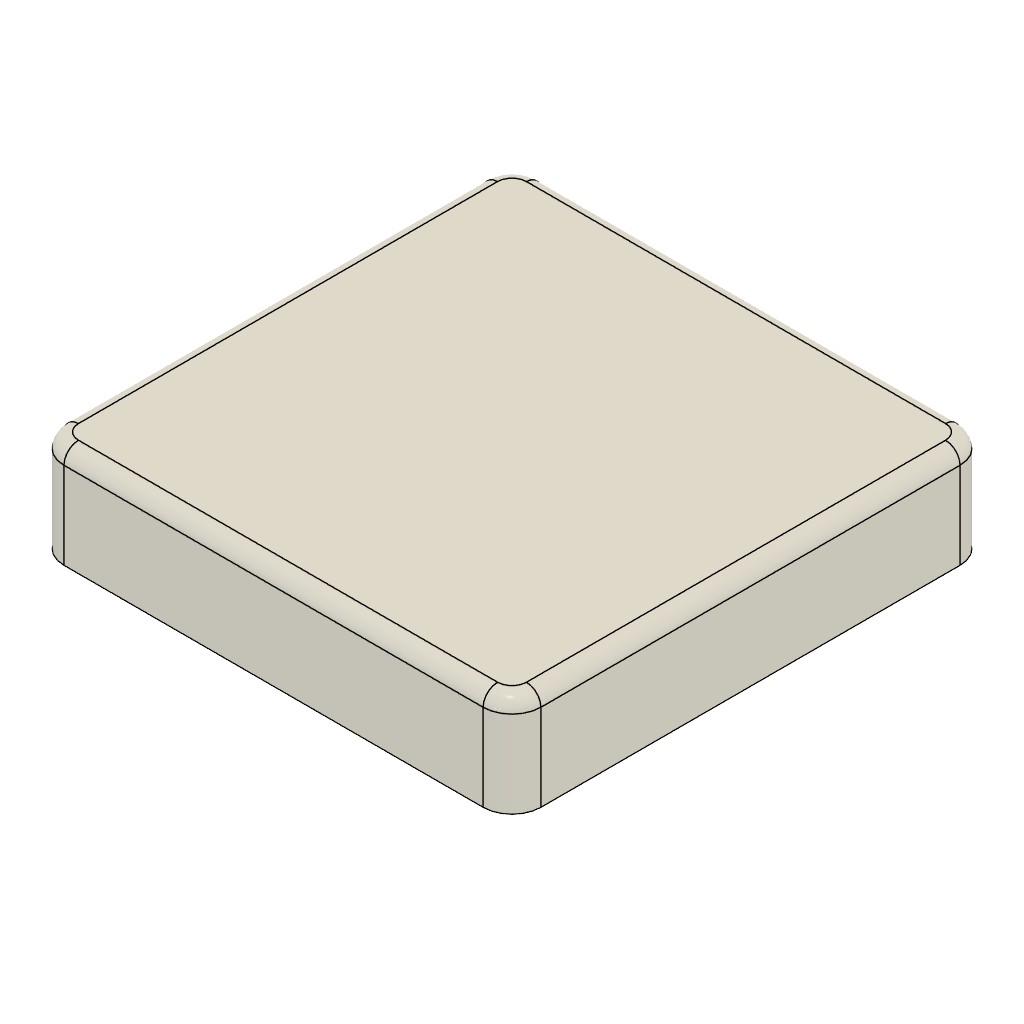
Assembly (Castor) (Autodesk Fusion 360 archive; units mm, degrees)
design "Keycap (1u)" references "_Globals"
part number: 2026-10-16-12-48-24-599
Autodesk Fusion 360 part; units mm, degrees
(part 1 of 5)
derive "Derived from _Globals"
sketch "Sketch1" plane through (0, 0, 0) normal (0, 1, 0) x (1, 0, 0)
  line L0 (-8.25, -8.25) -> (8.25, -8.25)
  line L1 (8.25, -8.25) -> (8.25, 8.25)
  line L2 (8.25, 8.25) -> (-8.25, 8.25)
  line L3 (-8.25, 8.25) -> (-8.25, -8.25)
  line L4 (-8.25, -8.25) -> (8.25, 8.25) construction
  line L5 (8.25, -8.25) -> (-8.25, 8.25) construction
  dimension "d17" = 16.5
  dimension "d18" = 16.5
  constraint horizontal L0
  constraint perpendicular L0 L1
  constraint parallel L0 L2
  constraint parallel L1 L3
  constraint coincident L4 origin
  constraint coincident L5 origin
  measures "d17" distance of L1.end L2.end
  measures "d18" distance of L0.end L1.end
extrude "Extrude1" add sketch "Sketch1" along normal blind 3.5
fillet "Fillet1" radius 1 4 edges at (8.25, 1.75, -8.25) (-8.25, 1.75, -8.25) (-8.25, 1.75, 8.25) (8.25, 1.75, 8.25)
fillet "Fillet2" radius 0.5 8 edges at (7.9571, 3.5, -7.9571) (0, 3.5, -8.25) (-7.9571, 3.5, -7.9571) (-8.25, 3.5, 0) (-7.9571, 3.5, 7.9571) (0, 3.5, 8.25) (7.9571, 3.5, 7.9571) (8.25, 3.5, 0)
sketch "Sketch2" plane through (0, 0, 0) normal (0, -1, 0) x (1, 0, 0)
  arc A0 (8.25, 7.25) -> (7.25, 8.25) centre (7.25, 7.25) ccw
  line L0 (7.25, 8.25) -> (-7.25, 8.25)
  arc A1 (-7.25, 8.25) -> (-8.25, 7.25) centre (-7.25, 7.25) ccw
  line L1 (-8.25, 7.25) -> (-8.25, -7.25)
  arc A2 (-8.25, -7.25) -> (-7.25, -8.25) centre (-7.25, -7.25) ccw
  line L2 (-7.25, -8.25) -> (7.25, -8.25)
  arc A3 (7.25, -8.25) -> (8.25, -7.25) centre (7.25, -7.25) ccw
  line L3 (8.25, -7.25) -> (8.25, 7.25)
  line L4 (-7.25, -7.25) -> (7.25, -7.25)
  line L5 (7.25, -7.25) -> (7.25, 7.25)
  line L6 (7.25, 7.25) -> (-7.25, 7.25)
  line L7 (-7.25, 7.25) -> (-7.25, -7.25)
extrude "Extrude2" cut sketch "Sketch2" against normal blind 2.05 contours L4 L5 L6 L7
fillet "Fillet3" radius 0.5 4 edges at (-7.25, 1.025, 7.25) (7.25, 1.025, 7.25) (7.25, 1.025, -7.25) (-7.25, 1.025, -7.25)
sketch "Sketch3" plane through (0, 2.05, 0) normal (0, -1, 0) x (1, 0, 0)
  arc A0 (-7.25, -6.75) -> (-6.75, -7.25) centre (-6.75, -6.75) ccw
  line L0 (-6.75, -7.25) -> (6.75, -7.25)
  arc A1 (6.75, -7.25) -> (7.25, -6.75) centre (6.75, -6.75) ccw
  line L1 (7.25, -6.75) -> (7.25, 6.75)
  arc A2 (7.25, 6.75) -> (6.75, 7.25) centre (6.75, 6.75) ccw
  line L2 (6.75, 7.25) -> (-6.75, 7.25)
  arc A3 (-6.75, 7.25) -> (-7.25, 6.75) centre (-6.75, 6.75) ccw
  line L3 (-7.25, 6.75) -> (-7.25, -6.75)
  circle A4 centre (0, 0) radius 2.7
  line L4 (0, 0) -> (0, 2.05) construction
  line L5 (-0.7, 2.05) -> (0.7, 2.05)
  line L6 (0.7, 2.05) -> (0.7, 0.7)
  line L7 (0.7, 0.7) -> (2.05, 0.7)
  line L8 (-2.05, -0.7) -> (-2.05, 0.7)
  line L9 (-2.05, 0.7) -> (-0.7, 0.7)
  line L10 (-0.7, 0.7) -> (-0.7, 2.05)
  line L11 (0.7, -2.05) -> (-0.7, -2.05)
  line L12 (-0.7, -2.05) -> (-0.7, -0.7)
  line L13 (-0.7, -0.7) -> (-2.05, -0.7)
  line L14 (2.05, 0.7) -> (2.05, -0.7)
  line L15 (2.05, -0.7) -> (0.7, -0.7)
  line L16 (0.7, -0.7) -> (0.7, -2.05)
  dimension "d32" = 5.4
  dimension "d33" = 2.05
  dimension "d34" = 1.4
  dimension "d35" = 1.35
  dimension "d36" = 1.35
  dimension "d38" = 360
  constraint coincident A4.centre L4.start
  constraint vertical L4
  constraint horizontal L5
  constraint midpoint L4.end L5
  constraint perpendicular L5 L6
  constraint perpendicular L6 L7
  measures "d32" diameter of A4
  measures "d33" distance of A4.centre L4.end
  measures "d34" distance of L5.start L5.end
  measures "d35" distance of L5.end L6.end
  measures "d36" distance of L6.end L7.end
extrude "Extrude3" add sketch "Sketch3" along normal blind 3.35 contours A4
fillet "Fillet4" radius 0.1 1 edges at (-2.5173, -1.3, -0.9764)
fillet "Fillet5" radius 0.1 4 edges at (0.7, 0.375, -0.7) (-0.7, 0.375, -0.7) (0.7, 0.375, 0.7) (-0.7, 0.375, 0.7)
equation "keycap_size_Ref = 16.5 mm"
equation "keycap_thickness_Ref = 3.5 mm" comment "Keycap thickness without stem"
equation "keycap_full_thickness_Ref = 4.8 mm" comment "Keycap thickness from stem to top"
equation "keycap_top_fillet_Ref1 = 0.5 mm"
equation "keycap_side_fillet_Ref1 = 1 mm"
equation "stem_fillet_Ref = 0.1 mm"
equation "stem_diameter_Ref = 5.5 mm"
equation "stem_cross_length_Ref = 4 mm"
equation "stem_cross_width_Ref = 1.3 mm"
equation "stem_offset_Ref = 0.1 mm"
equation "d17 = keycap_size_Ref"
equation "d18 = keycap_size_Ref"
equation "d19 = keycap_thickness_Ref"
equation "keycap_side_width_Ref = 1 mm"
equation "d23 = keycap_side_fillet_Ref1"
equation "d25 = keycap_top_fillet_Ref1"
equation "d26 = -keycap_side_width_Ref"
equation "keycap_inner_thickness_Ref = keycap_full_thickness_Ref - 3.35 mm"
equation "d28 = -( keycap_thickness_Ref - keycap_inner_thickness_Ref )"
equation "d31 = keycap_side_fillet_Ref1 * 0.5"
equation "d32 = stem_diameter_Ref - stem_offset_Ref"
equation "d33 = ( stem_cross_length_Ref + stem_offset_Ref ) * 0.5"
equation "d34 = stem_cross_width_Ref + stem_offset_Ref"
equation "d35 = ( stem_cross_length_Ref + stem_offset_Ref ) * 0.5 - ( stem_cross_width_Ref + stem_offset_Ref ) * 0.5"
equation "d36 = ( stem_cross_length_Ref + stem_offset_Ref ) * 0.5 - ( stem_cross_width_Ref + stem_offset_Ref ) * 0.5"
equation "d39 = keycap_full_thickness_Ref - keycap_inner_thickness_Ref"
equation "d42 = stem_fillet_Ref"
equation "d44 = stem_fillet_Ref"
equation "switch_size_Ref = 19.05 mm"
named bodies: "Main"

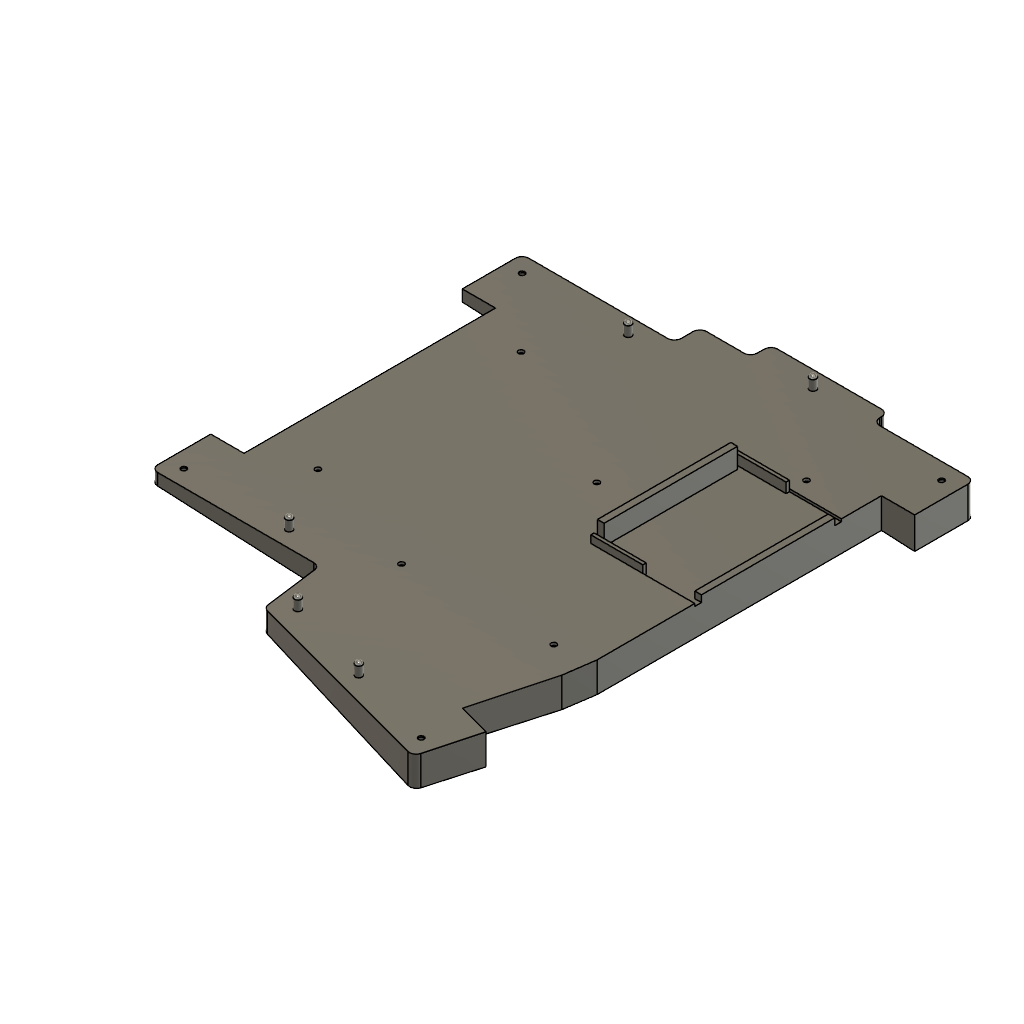
design "Case Bottom (Castor)" references "_Globals"
part number: 2026-10-18-17-09-08-420
Autodesk Fusion 360 part; units mm, degrees
derive "ExternalDerived1"
sketch "Sketch1" plane through (0, 0, 0) normal (0, 1, 0) x (1, 0, 0)
  line L0 (-9.525, 57.15) -> (-66.675, 57.15) construction
  line L1 (-66.675, 57.15) -> (-66.675, -57.15) construction
  line L2 (-66.675, -57.15) -> (-9.525, -57.15) construction
  line L3 (66.675, -45.72) -> (66.675, 57.15) construction
  line L4 (-66.675, 57.15) -> (-9.525, 57.15) construction
  line L5 (-9.525, 57.15) -> (-9.525, 66.675) construction
  line L6 (-9.525, 66.675) -> (9.525, 66.675) construction
  line L7 (9.525, 66.675) -> (9.525, 74.295) construction
  line L8 (9.525, 74.295) -> (28.575, 74.295) construction
  line L9 (28.575, 74.295) -> (28.575, 68.58) construction
  line L10 (28.575, 68.58) -> (66.675, 68.58) construction
  line L11 (66.675, 68.58) -> (66.675, 57.15) construction
  line L12 (-66.675, -57.15) -> (-9.525, -57.15) construction
  line L13 (-9.525, -57.15) -> (-9.525, -47.625) construction
  line L14 (-9.525, -47.625) -> (9.525, -47.625) construction
  line L15 (9.525, -47.625) -> (9.525, -45.72) construction
  line L16 (9.525, -45.72) -> (66.675, -45.72) construction
  line L17 (9.525, -47.625) -> (9.525, -47.73) construction
  line L18 (9.525, -47.73) -> (9.59, -47.73) construction
  line L19 (9.59, -47.73) -> (9.7259, -47.2229) construction
  line L20 (9.7259, -47.2229) -> (9.2188, -47.087) construction
  line L21 (9.2188, -47.087) -> (27.6197, -52.0175) construction
  line L22 (27.6197, -52.0175) -> (22.6892, -70.4184) construction
  line L23 (22.6892, -70.4184) -> (4.2883, -65.4879) construction
  line L24 (4.2883, -65.4879) -> (9.2188, -47.087) construction
  line L25 (27.6197, -52.0175) -> (64.4214, -61.8785) construction
  line L26 (64.4214, -61.8785) -> (54.5604, -98.6803) construction
  line L27 (54.5604, -98.6803) -> (-0.6422, -83.8888) construction
  line L28 (-0.6422, -83.8888) -> (4.2883, -65.4879) construction
  line L29 (-66.675, -57.15) -> (-69.15, -57.15) construction
  line L30 (-69.15, -57.15) -> (-69.15, -59.625) construction
  line L31 (-9.525, -57.15) -> (-7.05, -57.15) construction
  line L32 (-7.05, -57.15) -> (-7.05, -59.625) construction
  line L33 (-0.6422, -83.8888) -> (-1.2828, -86.2794) construction
  line L34 (-1.2828, -86.2794) -> (-3.6735, -85.6389) construction
  line L35 (54.5604, -98.6803) -> (53.9198, -101.071) construction
  line L36 (53.9198, -101.071) -> (56.3105, -101.7115) construction
  line L37 (64.4214, -61.8785) -> (65.062, -59.4879) construction
  line L38 (65.062, -59.4879) -> (67.4527, -60.1284) construction
  line L39 (66.675, -45.72) -> (66.675, -48.195) construction
  line L40 (66.675, -48.195) -> (69.15, -48.195) construction
  line L41 (66.675, 68.58) -> (66.675, 71.055) construction
  line L42 (66.675, 71.055) -> (69.15, 71.055) construction
  line L43 (28.575, 68.58) -> (31.05, 68.58) construction
  line L44 (31.05, 68.58) -> (31.05, 71.055) construction
  line L45 (28.575, 74.295) -> (28.575, 76.77) construction
  line L46 (28.575, 76.77) -> (31.05, 76.77) construction
  line L47 (9.525, 74.295) -> (9.525, 76.77) construction
  line L48 (9.525, 76.77) -> (7.05, 76.77) construction
  line L49 (9.525, 66.675) -> (7.05, 66.675) construction
  line L50 (7.05, 66.675) -> (7.05, 69.15) construction
  line L51 (-9.525, 66.675) -> (-12, 66.675) construction
  line L52 (-12, 66.675) -> (-12, 69.15) construction
  line L53 (-9.525, 57.15) -> (-12, 57.15) construction
  line L54 (-12, 57.15) -> (-12, 59.625) construction
  line L55 (-66.675, 57.15) -> (-69.15, 57.15) construction
  line L56 (-69.15, 57.15) -> (-69.15, 59.625) construction
  line L57 (-69.15, 59.625) -> (-12, 59.625)
  line L58 (-12, 59.625) -> (-12, 69.15)
  line L59 (-12, 69.15) -> (7.05, 69.15)
  line L60 (7.05, 69.15) -> (7.05, 76.77)
  line L61 (31.05, 76.77) -> (7.05, 76.77)
  line L62 (31.05, 71.055) -> (31.05, 76.77)
  line L63 (31.05, 71.055) -> (69.15, 71.055)
  line L64 (69.15, 71.055) -> (69.15, -48.195)
  line L65 (69.15, -48.195) -> (67.4527, -60.1284)
  line L66 (67.4527, -60.1284) -> (56.3105, -101.7115)
  line L67 (56.3105, -101.7115) -> (-3.6735, -85.6389)
  line L68 (-3.6735, -85.6389) -> (-7.05, -59.625)
  line L69 (-7.05, -59.625) -> (-69.15, -59.625)
  line L70 (-69.15, -59.625) -> (-69.15, 59.625)
  line L71 (-22, 79.15) -> (-2.95, 79.15)
  line L72 (-2.95, 79.15) -> (-2.95, 86.77)
  line L73 (41.05, 86.77) -> (-2.95, 86.77)
  line L74 (41.05, 81.055) -> (41.05, 86.77)
  line L75 (41.05, 81.055) -> (79.15, 81.055)
  line L76 (79.15, 81.055) -> (79.15, -48.9026)
  line L77 (79.15, -48.9026) -> (77.2681, -62.1339)
  line L78 (77.2681, -62.1339) -> (63.3816, -113.959)
  line L79 (63.3816, -113.959) -> (-12.7285, -93.5653)
  line L80 (-12.7285, -93.5653) -> (-15.8359, -69.625)
  line L81 (-15.8359, -69.625) -> (-79.15, -69.625)
  line L82 (-79.15, -69.625) -> (-79.15, 69.625)
  line L83 (-79.15, 69.625) -> (-22, 69.625)
  line L84 (-22, 69.625) -> (-22, 79.15)
  line L85 (-66.675, 57.15) -> (-9.525, 57.15)
  line L86 (-9.525, 57.15) -> (-9.525, 66.675)
  line L87 (-9.525, 66.675) -> (9.525, 66.675)
  line L88 (9.525, 66.675) -> (9.525, 74.295)
  line L89 (28.575, 74.295) -> (9.525, 74.295)
  line L90 (28.575, 68.58) -> (28.575, 74.295)
  line L91 (28.575, 68.58) -> (66.675, 68.58)
  line L92 (66.675, 68.58) -> (66.675, -48.0199)
  line L93 (66.675, -48.0199) -> (65.0234, -59.6321)
  line L94 (65.0234, -59.6321) -> (54.5604, -98.6803)
  line L95 (54.5604, -98.6803) -> (-1.4324, -83.6771)
  line L96 (-1.4324, -83.6771) -> (-4.8755, -57.15)
  line L97 (-4.8755, -57.15) -> (-66.675, -57.15)
  line L98 (-66.675, -57.15) -> (-66.675, 57.15)
  line L99 (-66.675, 57.15) -> (-66.675, 47.15) construction
  line L100 (-66.675, 47.15) -> (-79.15, 47.15)
  line L101 (-66.675, -57.15) -> (-66.675, -47.15) construction
  line L102 (-66.675, -47.15) -> (-79.15, -47.15)
  line L103 (54.5604, -98.6803) -> (57.1486, -89.021) construction
  line L104 (57.1486, -89.021) -> (69.1985, -92.2498)
  line L105 (66.675, 68.58) -> (66.675, 58.58) construction
  line L106 (66.675, 58.58) -> (79.15, 58.58)
  dimension "d54" = 114.3
  dimension "d55" = 57.15
  dimension "d56" = 9.525
  dimension "d57" = 19.05
  dimension "d58" = 7.62
  dimension "d59" = 19.05
  dimension "d60" = 5.715
  dimension "d61" = 38.1
  dimension "d62" = 57.15
  dimension "d63" = 9.525
  dimension "d64" = 19.05
  dimension "d65" = 1.905
  dimension "d66" = 0.105
  dimension "d67" = 0.065
  dimension "d68" = 0.525
  dimension "d69" = 0.525
  dimension "d70" = 19.05
  dimension "d71" = 19.05
  dimension "d72" = 38.1
  dimension "d73" = 38.1
  dimension "d74" = 57.15
  dimension "d75" = 2.475
  dimension "d76" = 2.475
  dimension "d77" = 2.475
  dimension "d78" = 2.475
  dimension "d79" = 2.475
  dimension "d80" = 2.475
  dimension "d81" = 2.475
  dimension "d82" = 2.475
  dimension "d83" = 2.475
  dimension "d84" = 2.475
  dimension "d85" = 2.475
  dimension "d86" = 2.475
  dimension "d87" = 2.475
  dimension "d88" = 2.475
  dimension "d89" = 2.475
  dimension "d90" = 2.475
  dimension "d91" = 2.475
  dimension "d92" = 2.475
  dimension "d93" = 2.475
  dimension "d94" = 2.475
  dimension "d95" = 2.475
  dimension "d96" = 2.475
  dimension "d97" = 2.475
  dimension "d98" = 2.475
  dimension "d99" = 2.475
  dimension "d100" = 2.475
  dimension "d101" = 2.475
  dimension "d102" = 2.475
  dimension "d104" = 2.475
  dimension "d107" = 10
  dimension "d108" = 10
  dimension "d109" = 10
  dimension "d110" = 10
  constraint horizontal L0
  constraint perpendicular L0 L1
  constraint parallel L0 L2
  constraint parallel L1 L3
  constraint perpendicular L4 L5
  constraint perpendicular L5 L6
  constraint perpendicular L6 L7
  constraint perpendicular L7 L8
  constraint perpendicular L6 L9
  constraint perpendicular L9 L10
  constraint perpendicular L12 L13
  constraint perpendicular L13 L14
  constraint perpendicular L12 L15
  constraint perpendicular L3 L16
  constraint perpendicular L14 L17
  constraint perpendicular L15 L18
  constraint perpendicular L19 L20
  constraint collinear L20 L21
  constraint parallel L21 L23
  constraint parallel L22 L24
  constraint perpendicular L22 L23
  constraint perpendicular L22 L25
  constraint perpendicular L25 L26
  constraint perpendicular L26 L27
  constraint perpendicular L1 L29
  constraint perpendicular L29 L30
  constraint perpendicular L13 L31
  constraint perpendicular L31 L32
  constraint perpendicular L27 L33
  constraint perpendicular L28 L34
  constraint perpendicular L27 L35
  constraint perpendicular L35 L36
  constraint perpendicular L25 L37
  constraint perpendicular L37 L38
  constraint perpendicular L16 L39
  constraint perpendicular L3 L40
  constraint perpendicular L10 L41
  constraint perpendicular L11 L42
  constraint coincident L10 L43.end
  constraint perpendicular L43 L44
  constraint perpendicular L8 L45
  constraint perpendicular L45 L46
  constraint perpendicular L8 L47
  constraint perpendicular L47 L48
  constraint coincident L6 L49.end
  constraint perpendicular L6 L50
  constraint perpendicular L5 L51
  constraint perpendicular L51 L52
  constraint coincident L4 L53.end
  constraint perpendicular L53 L54
  constraint perpendicular L1 L55
  constraint perpendicular L4 L56
  constraint perpendicular L62 L63
  constraint coincident L98 L99.end
  constraint coincident L82 L100.end
  constraint perpendicular L82 L100
  constraint coincident L98 L101.end
  constraint coincident L82 L102.end
  constraint perpendicular L82 L102
  constraint coincident L26 L103.end
  constraint coincident L78 L104.end
  constraint perpendicular L78 L104
  constraint coincident L11 L105.end
  constraint coincident L76 L106.end
  constraint perpendicular L76 L106
  measures "d54" distance of L0.end L1.end
  measures "d55" distance of L0.end L0.start
  measures "d56" distance of L0.start L5.end
  measures "d57" distance of L5.end L6.end
  measures "d58" distance of L6.end L7.end
  measures "d59" distance of L7.end L8.end
  measures "d60" distance of L8.end L9.end
  measures "d61" distance of L9.end L10.end
  measures "d62" distance of L1.end L2.end
  measures "d63" distance of L2.end L13.end
  measures "d64" distance of L13.end L14.end
  measures "d65" distance of L14.end L15.end
  measures "d66" distance of L14.end L17.end
  measures "d67" distance of L17.end L18.end
  measures "d68" distance of L18.end L19.end
  measures "d69" distance of L19.end L20.end
  measures "d70" distance of L20.end L21.end
  measures "d71" distance of L20.end L23.end
  measures "d72" distance of L21.end L25.end
  measures "d73" distance of L25.end L26.end
  measures "d74" distance of L26.end L27.end
  measures "d75" distance of L1.end L29.end
  measures "d76" distance of L29.end L30.end
  measures "d77" distance of L2.end L31.end
  measures "d78" distance of L31.end L32.end
  measures "d79" distance of L27.end L33.end
  measures "d80" distance of L33.end L34.end
  measures "d81" distance of L26.end L35.end
  measures "d82" distance of L35.end L36.end
  measures "d83" distance of L25.end L37.end
  measures "d84" distance of L37.end L38.end
  measures "d85" distance of L3.start L39.end
  measures "d86" distance of L39.end L40.end
  measures "d87" distance of L10.end L41.end
  measures "d88" distance of L41.end L42.end
  measures "d89" distance of L9.end L43.end
  measures "d90" distance of L43.end L44.end
  measures "d91" distance of L8.end L45.end
  measures "d92" distance of L45.end L46.end
  measures "d93" distance of L7.end L47.end
  measures "d94" distance of L47.end L48.end
  measures "d95" distance of L6.end L49.end
  measures "d96" distance of L49.end L50.end
  measures "d97" distance of L5.end L51.end
  measures "d98" distance of L51.end L52.end
  measures "d99" distance of L0.start L53.end
  measures "d100" distance of L53.end L54.end
  measures "d101" distance of L0.end L55.end
  measures "d102" distance of L55.end L56.end
  measures "d107" distance of L0.end L99.end
  measures "d108" distance of L1.end L101.end
  measures "d109" distance of L26.end L103.end
  measures "d110" distance of L10.end L105.end
extrude "Extrude1" add sketch "Sketch1" against normal blind 11.8975
extrude "Extrude2" cut sketch "Sketch1" against normal through all contours L70 L98 L100 L102 | L70 L82 L100 L102 | L64 L65 L66 L92 L93 L94 L104 L106 | L64 L65 L66 L76 L77 L78 L104 L106
sketch "Sketch2" plane through (0, -11.8975, 0) normal (0, -1, 0) x (1, 0, 0)
  line L0 (-66.675, -47.15) -> (-79.15, -47.15)
  line L1 (-79.15, -47.15) -> (-79.15, -69.625)
  line L2 (-79.15, -69.625) -> (-22, -69.625)
  line L3 (-22, -69.625) -> (-22, -79.15)
  line L4 (-22, -79.15) -> (-2.95, -79.15)
  line L5 (-2.95, -79.15) -> (-2.95, -86.77)
  line L6 (-2.95, -86.77) -> (41.05, -86.77)
  line L7 (41.05, -86.77) -> (41.05, -81.055)
  line L8 (41.05, -81.055) -> (79.15, -81.055)
  line L9 (79.15, -81.055) -> (79.15, -58.58)
  line L10 (79.15, -58.58) -> (66.675, -58.58)
  line L11 (66.675, -58.58) -> (66.675, 48.0199)
  line L12 (66.675, 48.0199) -> (65.0234, 59.6321)
  line L13 (65.0234, 59.6321) -> (57.1486, 89.021)
  line L14 (57.1486, 89.021) -> (69.1985, 92.2498)
  line L15 (69.1985, 92.2498) -> (63.3816, 113.959)
  line L16 (63.3816, 113.959) -> (-12.7285, 93.5653)
  line L17 (-12.7285, 93.5653) -> (-15.8359, 69.625)
  line L18 (-15.8359, 69.625) -> (-79.15, 69.625)
  line L19 (-79.15, 69.625) -> (-79.15, 47.15)
  line L20 (-79.15, 47.15) -> (-66.675, 47.15)
  line L21 (-66.675, 47.15) -> (-66.675, -47.15)
  line L22 (79.15, -81.055) -> (79.15, -71.055) construction
  line L23 (79.15, -71.055) -> (69.15, -71.055) construction
  line L24 (69.15, -71.055) -> (79.15, -81.055) construction
  circle A0 centre (79.15, -81.055) radius 8.75 construction
  line L25 (-79.15, -69.625) -> (-69.15, -69.625) construction
  line L26 (-69.15, -69.625) -> (-69.15, -59.625) construction
  line L27 (-69.15, -59.625) -> (-79.15, -69.625) construction
  circle A1 centre (-79.15, -69.625) radius 8.75 construction
  line L28 (63.3816, 113.959) -> (53.7223, 111.3708) construction
  line L29 (53.7223, 111.3708) -> (56.3105, 101.7115) construction
  line L30 (56.3105, 101.7115) -> (63.3816, 113.959) construction
  circle A2 centre (63.3816, 113.959) radius 8.75 construction
  line L31 (-79.15, 69.625) -> (-69.15, 69.625) construction
  line L32 (-69.15, 69.625) -> (-69.15, 59.625) construction
  line L33 (-69.15, 59.625) -> (-79.15, 69.625) construction
  circle A3 centre (-79.15, 69.625) radius 8.75 construction
  circle A4 centre (-72.9628, 63.4378) radius 1.025
  circle A5 centre (-72.9628, 63.4378) radius 2.075
  circle A6 centre (59.0066, 106.3813) radius 2.075
  circle A7 centre (59.0066, 106.3813) radius 1.025
  circle A8 centre (72.9628, -74.8678) radius 2.075
  circle A9 centre (72.9628, -74.8678) radius 1.025
  circle A10 centre (-72.9628, -63.4378) radius 2.075
  circle A11 centre (-72.9628, -63.4378) radius 1.025
  line L34 (-69.15, -59.625) -> (-47.625, -59.625) construction
  line L35 (-47.625, -59.625) -> (-47.625, -37.725) construction
  line L36 (-69.15, 59.625) -> (-47.625, 59.625) construction
  line L37 (-47.625, 59.625) -> (-47.625, 38.475) construction
  line L38 (69.15, -71.055) -> (47.625, -71.055) construction
  line L39 (47.625, -71.055) -> (47.625, -49.53) construction
  line L40 (-47.625, -59.625) -> (8.975, -59.625) construction
  line L41 (8.975, -59.625) -> (8.975, -9.525) construction
  line L42 (69.15, -71.055) -> (69.15, 45.72) construction
  line L43 (69.15, 45.72) -> (53.5781, 45.72) construction
  line L44 (53.5781, 45.72) -> (53.5781, 51.1969) construction
  line L45 (-47.625, 59.625) -> (-1.1906, 59.625) construction
  line L46 (-1.1906, 59.625) -> (-1.1906, 53.5781) construction
  circle A12 centre (-1.1906, 53.5781) radius 1.025
  circle A13 centre (-1.1906, 53.5781) radius 1.75
  circle A14 centre (-47.625, 38.475) radius 1.025
  circle A15 centre (-47.625, 38.475) radius 1.75
  circle A16 centre (53.5781, 51.1969) radius 1.025
  circle A17 centre (53.5781, 51.1969) radius 1.75
  circle A18 centre (8.975, -9.525) radius 1.025
  circle A19 centre (8.975, -9.525) radius 1.75
  circle A20 centre (47.625, -49.53) radius 1.025
  circle A21 centre (47.625, -49.53) radius 1.75
  circle A22 centre (-47.625, -37.725) radius 1.025
  circle A23 centre (-47.625, -37.725) radius 1.75
  dimension "d112" = 10
  dimension "d113" = 10
  dimension "d114" = 17.5
  dimension "d115" = 10
  dimension "d116" = 10
  dimension "d117" = 17.5
  dimension "d118" = 10
  dimension "d119" = 10
  dimension "d120" = 17.5
  dimension "d121" = 10
  dimension "d122" = 10
  dimension "d123" = 17.5
  dimension "d124" = 2.05
  dimension "d125" = 4.15
  dimension "d126" = 4.15
  dimension "d127" = 2.05
  dimension "d128" = 4.15
  dimension "d129" = 2.05
  dimension "d130" = 4.15
  dimension "d131" = 2.05
  dimension "d134" = 21.525
  dimension "d135" = 21.9
  dimension "d138" = 21.525
  dimension "d139" = 21.15
  dimension "d140" = 21.525
  dimension "d141" = 21.525
  dimension "d142" = 56.6
  dimension "d146" = 50.1
  dimension "d147" = 116.775
  dimension "d148" = 15.5719
  dimension "d149" = 5.4769
  dimension "d150" = 46.4344
  dimension "d151" = 6.0469
  dimension "d152" = 2.05
  dimension "d153" = 3.5
  dimension "d154" = 2.05
  dimension "d155" = 3.5
  dimension "d156" = 2.05
  dimension "d157" = 3.5
  dimension "d158" = 2.05
  dimension "d159" = 3.5
  dimension "d160" = 2.05
  dimension "d161" = 3.5
  dimension "d162" = 2.05
  dimension "d163" = 3.5
  constraint coincident L8.end L9.start
  constraint perpendicular L8 L22
  constraint perpendicular L9 L23
  constraint coincident L1.end L2.start
  constraint coincident L2 L25.end
  constraint perpendicular L2 L26
  constraint coincident L15.end L16.start
  constraint coincident L16 L28.end
  constraint perpendicular L16 L29
  constraint coincident L18.end L19.start
  constraint coincident L18 L31.end
  constraint perpendicular L18 L32
  constraint coincident A3 A4.centre
  constraint coincident L33 A4.centre
  constraint concentric A4 A5
  constraint coincident A2 A6.centre
  constraint coincident L30 A6.centre
  constraint concentric A6 A7
  constraint coincident A0 A8.centre
  constraint coincident L24 A8.centre
  constraint concentric A8 A9
  constraint coincident A1 A10.centre
  constraint coincident L27 A10.centre
  constraint concentric A10 A11
  constraint perpendicular L26 L34
  constraint perpendicular L34 L35
  constraint perpendicular L32 L36
  constraint perpendicular L36 L37
  constraint parallel L23 L38
  constraint perpendicular L38 L39
  constraint perpendicular L35 L40
  constraint perpendicular L40 L41
  constraint perpendicular L38 L42
  constraint perpendicular L42 L43
  constraint perpendicular L43 L44
  constraint perpendicular L37 L45
  constraint perpendicular L45 L46
  constraint coincident L46.end A12.centre
  constraint concentric A12 A13
  constraint coincident L37.end A14.centre
  constraint concentric A14 A15
  constraint coincident L44.end A16.centre
  constraint concentric A16 A17
  constraint coincident L41.end A18.centre
  constraint concentric A18 A19
  constraint coincident L39.end A20.centre
  constraint concentric A20 A21
  constraint coincident L35.end A22.centre
  measures "d112" distance of L8.end L22.end
  measures "d113" distance of L22.end L23.end
  measures "d114" diameter of A0
  measures "d115" distance of L1.end L25.end
  measures "d116" distance of L25.end L26.end
  measures "d117" diameter of A1
  measures "d118" distance of L15.end L28.end
  measures "d119" distance of L28.end L29.end
  measures "d120" diameter of A2
  measures "d121" distance of L18.end L31.end
  measures "d122" distance of L31.end L32.end
  measures "d123" diameter of A3
  measures "d124" diameter of A4
  measures "d125" diameter of A5
  measures "d126" diameter of A6
  measures "d127" diameter of A7
  measures "d128" diameter of A8
  measures "d129" diameter of A9
  measures "d130" diameter of A10
  measures "d131" diameter of A11
  measures "d134" distance of L26.end L34.end
  measures "d135" distance of L34.end L35.end
  measures "d138" distance of L32.end L36.end
  measures "d139" distance of L36.end L37.end
  measures "d140" distance of L23.end L38.end
  measures "d141" distance of L38.end L39.end
  measures "d142" distance of L34.end L40.end
  measures "d146" distance of L40.end L41.end
  measures "d147" distance of L23.end L42.end
  measures "d148" distance of L42.end L43.end
  measures "d149" distance of L43.end L44.end
  measures "d150" distance of L36.end L45.end
  measures "d151" distance of L45.end L46.end
  measures "d152" diameter of A12
  measures "d153" diameter of A13
  measures "d154" diameter of A14
  measures "d155" diameter of A15
  measures "d156" diameter of A16
  measures "d157" diameter of A17
  measures "d158" diameter of A18
  measures "d159" diameter of A19
  measures "d160" diameter of A20
  measures "d161" diameter of A21
  measures "d162" diameter of A22
  measures "d163" diameter of A23
extrude "Extrude3" cut sketch "Sketch2" against normal through all contours A4 | A7 | A9 | A11 | A12 | A14 | A16 | A18 | A20 | A22
sketch "Sketch3" plane through (0, 0, 0) normal (0, 1, 0) x (-1, 0, 0)
  line L0 (79.15, -47.15) -> (66.675, -47.15)
  line L1 (66.675, -47.15) -> (66.675, 47.15)
  line L2 (66.675, 47.15) -> (79.15, 47.15)
  line L3 (79.15, 47.15) -> (79.15, 69.625)
  line L4 (79.15, 69.625) -> (15.8359, 69.625)
  line L5 (15.8359, 69.625) -> (12.7285, 93.5653)
  line L6 (12.7285, 93.5653) -> (-63.3816, 113.959)
  line L7 (-63.3816, 113.959) -> (-69.1985, 92.2498)
  line L8 (-69.1985, 92.2498) -> (-57.1486, 89.021)
  line L9 (-57.1486, 89.021) -> (-65.0234, 59.6321)
  line L10 (-65.0234, 59.6321) -> (-66.675, 48.0199)
  line L11 (-66.675, 48.0199) -> (-66.675, -58.58)
  line L12 (-66.675, -58.58) -> (-79.15, -58.58)
  line L13 (-79.15, -58.58) -> (-79.15, -81.055)
  line L14 (-79.15, -81.055) -> (-41.05, -81.055)
  line L15 (-41.05, -81.055) -> (-41.05, -86.77)
  line L16 (-41.05, -86.77) -> (2.95, -86.77)
  line L17 (2.95, -86.77) -> (2.95, -79.15)
  line L18 (2.95, -79.15) -> (22, -79.15)
  line L19 (22, -79.15) -> (22, -69.625)
  line L20 (22, -69.625) -> (79.15, -69.625)
  line L21 (79.15, -69.625) -> (79.15, -47.15)
  circle A0 centre (72.9628, -63.4378) radius 1.025
  circle A1 centre (-8.975, -9.525) radius 1.025
  circle A2 centre (1.1906, 53.5781) radius 1.025
  circle A3 centre (-53.5781, 51.1969) radius 1.025
  circle A4 centre (-47.625, -49.53) radius 1.025
  circle A5 centre (47.625, -37.725) radius 1.025
  circle A6 centre (72.9628, 63.4378) radius 1.025
  circle A7 centre (-59.0066, 106.3813) radius 1.025
  circle A8 centre (47.625, 38.475) radius 1.025
  circle A9 centre (-72.9628, -74.8678) radius 1.025
  line L22 (79.15, -69.625) -> (66.675, -69.625) construction
  line L23 (66.675, -69.625) -> (66.675, -57.15) construction
  line L24 (66.675, -57.15) -> (9.525, -57.15) construction
  line L25 (9.525, -57.15) -> (9.525, -69.625) construction
  line L26 (66.675, -57.15) -> (56.675, -57.15) construction
  line L27 (56.675, -57.15) -> (56.675, -69.625) construction
  line L28 (56.675, -63.3875) -> (9.525, -63.3875) construction
  circle A10 centre (33.1, -63.3875) radius 1.25
  line L29 (-19.05, -86.77) -> (-19.05, -74.295) construction
  circle A11 centre (-19.05, -80.5325) radius 1.25
  line L30 (-25.3265, 103.7622) -> (-28.5553, 91.7122) construction
  circle A12 centre (-26.9409, 97.7372) radius 1.25
  line L31 (-53.9198, 101.071) -> (3.6735, 85.6389) construction
  line L32 (3.6735, 85.6389) -> (12.7285, 93.5653) construction
  line L33 (3.6735, 85.6389) -> (-10.6659, 73.0867) construction
  line L34 (-57.1486, 89.021) -> (-54.5604, 98.6803) construction
  line L35 (-54.5604, 98.6803) -> (-53.9198, 101.071) construction
  line L36 (-54.5604, 98.6803) -> (1.4324, 83.6771) construction
  line L37 (79.15, 69.625) -> (66.675, 69.625) construction
  line L38 (66.675, 69.625) -> (66.675, 59.625) construction
  line L39 (66.675, 59.625) -> (66.675, 57.15) construction
  line L40 (66.675, 59.625) -> (7.05, 59.625) construction
  line L41 (7.05, 59.625) -> (15.8359, 69.625) construction
  line L42 (7.05, 59.625) -> (-0.857, 50.6253) construction
  line L43 (66.675, 57.15) -> (4.8755, 57.15) construction
  line L44 (4.8755, 57.15) -> (1.4324, 83.6771) construction
  line L45 (66.675, 69.625) -> (56.675, 69.625) construction
  line L46 (56.675, 69.625) -> (56.675, 57.15) construction
  line L47 (56.675, 63.3875) -> (10.3557, 63.3875) construction
  circle A13 centre (33.5154, 63.3875) radius 1.25
  line L48 (3.1539, 70.4135) -> (14.2822, 81.5952) construction
  line L49 (8.7181, 76.0044) -> (-26.9409, 97.7372) construction
  line L50 (-9.1114, 86.8708) -> (12.7285, 93.5653) construction
  line L51 (1.4324, 83.6771) -> (12.7285, 93.5653) construction
  line L52 (1.8086, 90.2181) -> (7.0804, 88.6212) construction
  line L53 (1.8086, 90.2181) -> (4.8871, 86.7012) construction
  line L54 (4.8871, 86.7012) -> (7.0804, 88.6212) construction
  circle A14 centre (5.9838, 87.6612) radius 1.25
  dimension "d165" = 12.475
  dimension "d166" = 12.475
  dimension "d167" = 57.15
  dimension "d168" = 12.475
  dimension "d169" = 10
  dimension "d170" = 2.5
  dimension "d171" = 12.475
  dimension "d172" = 2.5
  dimension "d173" = 12.475
  dimension "d174" = 2.5
  dimension "d175" = 12.475
  dimension "d177" = 59.625
  dimension "d178" = 10
  dimension "d179" = 2.475
  dimension "d180" = 12.475
  dimension "d181" = 10
  dimension "d182" = 2.475
  dimension "d184" = 59.625
  dimension "d185" = 10
  dimension "d186" = 2.5
  dimension "d187" = 2.5
  constraint coincident L20.end L21.start
  constraint coincident L20 L22.end
  constraint perpendicular L20 L23
  constraint perpendicular L23 L24
  constraint perpendicular L24 L25
  constraint coincident L24 L26.end
  constraint coincident L20 L27.end
  constraint perpendicular L20 L27
  constraint midpoint L27 L28.start
  constraint coincident L25 L28.end
  constraint perpendicular L25 L28
  constraint midpoint L28 A10.centre
  constraint midpoint L16 L29.start
  constraint perpendicular L16 L29
  constraint midpoint L29 A11.centre
  constraint midpoint L6 L30.start
  constraint perpendicular L6 L30
  constraint midpoint L30 A12.centre
  constraint coincident L5.end L6.start
  constraint parallel L32 L33
  constraint coincident L8.end L9.start
  constraint coincident L33 L36.end
  constraint perpendicular L34 L36
  constraint perpendicular L31 L35
  constraint coincident L3.end L4.start
  constraint coincident L4 L37.end
  constraint perpendicular L4 L38
  constraint parallel L38 L39
  constraint perpendicular L39 L40
  constraint coincident L4.end L5.start
  constraint parallel L41 L42
  constraint coincident L42 L43.end
  constraint perpendicular L39 L43
  constraint coincident L4 L45.end
  constraint coincident L43 L46.end
  constraint perpendicular L43 L46
  constraint midpoint L46 L47.start
  constraint coincident L41 L47.end
  constraint perpendicular L46 L47
  constraint midpoint L47 A13.centre
  constraint midpoint L44 L48.start
  constraint midpoint L5 L48.end
  constraint midpoint L48 L49.start
  constraint coincident A12.centre L49.end
  constraint midpoint L49 L50.start
  constraint midpoint L50 L52.start
  constraint midpoint L51 L52.end
  constraint coincident L32 L53.end
  constraint perpendicular L51 L53
  constraint midpoint L54 A14.centre
  measures "d165" distance of L20.end L22.end
  measures "d166" distance of L22.end L23.end
  measures "d167" distance of L23.end L24.end
  measures "d168" distance of L24.end L25.end
  measures "d169" distance of L23.end L26.end
  measures "d170" diameter of A10
  measures "d171" distance of L29.start L29.end
  measures "d172" diameter of A11
  measures "d173" distance of L30.start L30.end
  measures "d174" diameter of A12
  measures "d175" distance of L8.end L31.start
  measures "d177" distance of L31.start L31.end
  measures "d178" distance of L8.end L34.end
  measures "d179" distance of L31.start L34.end
  measures "d180" distance of L3.end L37.end
  measures "d181" distance of L37.end L38.end
  measures "d182" distance of L38.end L39.end
  measures "d184" distance of L38.end L40.end
  measures "d185" distance of L37.end L45.end
  measures "d186" diameter of A13
  measures "d187" diameter of A14
extrude "Extrude4" add sketch "Sketch3" along normal blind 5 contours A10 | A11 | A12 | A13 | A14
fillet "Fillet1" radius 1.25 5 edges at (-32.3499, 5, 62.9355) (-4.8184, 5, 87.2092) (28.1063, 5, 97.2852) (-31.9346, 5, -63.8395) (20.2154, 5, -80.9845)
extrude "Extrude5" cut sketch "Sketch2" against normal blind 11.3975 contours A5 | A6 | A8 | A10
extrude "Extrude6" cut sketch "Sketch2" against normal blind 10.8975 contours A13 | A15 | A17 | A19 | A21 | A23
sketch "Sketch4" plane through (0, 0, 0) normal (0, 1, 0) x (-1, 0, 0)
  circle A0 centre (-72.9628, -74.8678) radius 1.025
  circle A1 centre (47.625, 38.475) radius 1.025
  circle A2 centre (-59.0066, 106.3813) radius 1.025
  circle A3 centre (72.9628, 63.4378) radius 1.025
  circle A4 centre (47.625, -37.725) radius 1.025
  circle A5 centre (-47.625, -49.53) radius 1.025
  circle A6 centre (-53.5781, 51.1969) radius 1.025
  circle A7 centre (1.1906, 53.5781) radius 1.025
  circle A8 centre (-8.975, -9.525) radius 1.025
  circle A9 centre (72.9628, -63.4378) radius 1.025
  line L0 (79.15, -47.15) -> (66.675, -47.15)
  line L1 (66.675, -47.15) -> (66.675, 47.15)
  line L2 (66.675, 47.15) -> (79.15, 47.15)
  line L3 (79.15, 47.15) -> (79.15, 69.625)
  line L4 (79.15, 69.625) -> (15.8359, 69.625)
  line L5 (15.8359, 69.625) -> (12.7285, 93.5653)
  line L6 (12.7285, 93.5653) -> (-63.3816, 113.959)
  line L7 (-63.3816, 113.959) -> (-69.1985, 92.2498)
  line L8 (-69.1985, 92.2498) -> (-57.1486, 89.021)
  line L9 (-57.1486, 89.021) -> (-65.0234, 59.6321)
  line L10 (-65.0234, 59.6321) -> (-66.675, 48.0199)
  line L11 (-66.675, 48.0199) -> (-66.675, -58.58)
  line L12 (-66.675, -58.58) -> (-79.15, -58.58)
  line L13 (-79.15, -58.58) -> (-79.15, -81.055)
  line L14 (-79.15, -81.055) -> (-41.05, -81.055)
  line L15 (-41.05, -81.055) -> (-41.05, -86.77)
  line L16 (-41.05, -86.77) -> (2.95, -86.77)
  line L17 (2.95, -86.77) -> (2.95, -79.15)
  line L18 (2.95, -79.15) -> (22, -79.15)
  line L19 (22, -79.15) -> (22, -69.625)
  line L20 (22, -69.625) -> (79.15, -69.625)
  line L21 (79.15, -69.625) -> (79.15, -47.15)
  circle A10 centre (33.1, -63.3875) radius 1.25
  circle A11 centre (33.5154, 63.3875) radius 1.25
  circle A12 centre (-19.05, -80.5325) radius 1.25
  circle A13 centre (5.9838, 87.6612) radius 1.25
  circle A14 centre (-26.9409, 97.7372) radius 1.25
  line L22 (-79.15, -81.055) -> (-66.675, -81.055) construction
  line L23 (-66.675, -81.055) -> (-66.675, -68.58) construction
  line L24 (-66.675, -68.58) -> (-66.675, -43.58) construction
  line L25 (-66.675, -43.58) -> (-27.675, -43.58)
  line L26 (-27.675, -43.58) -> (-27.675, 11.42)
  line L27 (-27.675, 11.42) -> (-66.675, 11.42)
  line L28 (-66.675, 11.42) -> (-66.675, -43.58)
  line L29 (-27.675, -43.58) -> (-66.675, -43.58)
  line L30 (-66.675, -43.58) -> (-66.675, -41.08)
  line L31 (-66.675, -41.08) -> (-27.675, -41.08)
  line L32 (-27.675, -41.08) -> (-27.675, -43.58)
  line L33 (-27.675, 11.42) -> (-66.675, 11.42)
  line L34 (-66.675, 11.42) -> (-66.675, 8.92)
  line L35 (-66.675, 8.92) -> (-27.675, 8.92)
  line L36 (-27.675, 8.92) -> (-27.675, 11.42)
  line L37 (-66.675, 8.92) -> (-64.175, 8.92)
  line L38 (-64.175, 8.92) -> (-64.175, -41.08)
  line L39 (-64.175, -41.08) -> (-66.675, -41.08)
  line L40 (-66.675, -41.08) -> (-66.675, 8.92)
  dimension "d196" = 12.475
  dimension "d197" = 12.475
  dimension "d198" = 25
  dimension "d199" = 39
  dimension "d200" = 55
  dimension "d201" = 2.5
  dimension "d202" = 2.5
  dimension "d203" = 2.5
  constraint coincident L13.end L14.start
  constraint coincident L14 L22.end
  constraint perpendicular L14 L23
  constraint parallel L11 L24
  constraint horizontal L25
  constraint vertical L26
  constraint horizontal L27
  constraint vertical L28
  constraint horizontal L29
  constraint vertical L30
  constraint horizontal L31
  constraint vertical L32
  constraint coincident L28 L30.end
  constraint horizontal L33
  constraint vertical L34
  constraint horizontal L35
  constraint vertical L36
  constraint coincident L28 L34.end
  constraint horizontal L37
  constraint vertical L38
  constraint horizontal L39
  constraint vertical L40
  constraint coincident L31 L38.end
  measures "d196" distance of L13.end L22.end
  measures "d197" distance of L22.end L23.end
  measures "d198" distance of L23.end L24.end
  measures "d199" distance of L24.end L25.end
  measures "d200" distance of L24.end L27.end
  measures "d201" distance of L25.end L31.end
  measures "d202" distance of L26.end L35.end
  measures "d203" distance of L34.end L37.end
extrude "Extrude7" cut sketch "Sketch4" against normal blind 0.95 contours L11 L25 L26 L28 L29 L30 L31 L32 L39 | L11 L26 L27 L28 L33 L34 L35 L36 L37 | L11 L28 L31 L35 L37 L38 L39 L40 | L26 L31 L35 L38
sketch "Sketch5" plane through (0, -0.95, 0) normal (0, 1, 0) x (-1, 0, 0)
  line L0 (-27.675, -43.58) -> (-27.675, 11.42)
  line L1 (-27.675, 11.42) -> (-66.675, 11.42)
  line L2 (-66.675, 11.42) -> (-66.675, -43.58)
  line L3 (-66.675, -43.58) -> (-27.675, -43.58)
  line L4 (-27.675, -43.58) -> (-47.175, -43.58)
  line L5 (-47.175, -43.58) -> (-47.175, -42.33)
  line L6 (-47.175, -42.33) -> (-27.675, -42.33)
  line L7 (-27.675, -42.33) -> (-27.675, -43.58)
  line L8 (-27.675, -16.08) -> (-66.675, -16.08) construction
  line L9 (-27.675, 11.42) -> (-47.175, 11.42)
  line L10 (-47.175, 11.42) -> (-47.175, 10.17)
  line L11 (-47.175, 10.17) -> (-27.675, 10.17)
  line L12 (-27.675, 10.17) -> (-27.675, 11.42)
  line L13 (-66.675, -43.58) -> (-66.675, -41.08) construction
  line L14 (-66.675, -41.08) -> (-64.175, -41.08)
  line L15 (-64.175, -41.08) -> (-64.175, 8.92)
  line L16 (-64.175, 8.92) -> (-66.675, 8.92)
  line L17 (-66.675, 8.92) -> (-66.675, -41.08)
  line L18 (-27.675, -42.33) -> (-27.675, -41.08) construction
  line L19 (-27.675, -41.08) -> (-30.175, -41.08)
  line L20 (-30.175, -41.08) -> (-30.175, 8.92)
  line L21 (-30.175, 8.92) -> (-27.675, 8.92)
  line L22 (-27.675, 8.92) -> (-27.675, -41.08)
  dimension "d206" = 19.5
  dimension "d207" = 1.25
  dimension "d208" = 2.5
  dimension "d209" = 2.5
  dimension "d210" = 50
  dimension "d218" = 1.25
  dimension "d219" = 2.5
  dimension "d220" = 50
  constraint horizontal L4
  constraint vertical L5
  constraint horizontal L6
  constraint vertical L7
  constraint coincident L0.start L3.end
  constraint midpoint L0 L8.start
  constraint midpoint L2 L8.end
  constraint symmetric L0.start L8 L0.end
  constraint symmetric L4.end L8 L9.end
  constraint symmetric L5.end L8 L10.end
  constraint symmetric L6.end L8 L11.end
  constraint coincident L2.end L3.start
  constraint coincident L2 L13.end
  constraint horizontal L14
  constraint vertical L15
  constraint horizontal L16
  constraint vertical L17
  constraint perpendicular L6 L18
  constraint horizontal L19
  constraint vertical L20
  constraint horizontal L21
  constraint vertical L22
  measures "d206" distance of L0.start L4.end
  measures "d207" distance of L0.start L6.end
  measures "d208" distance of L2.end L13.end
  measures "d209" distance of L13.end L14.end
  measures "d210" distance of L13.end L16.end
  measures "d218" distance of L6.end L18.end
  measures "d219" distance of L18.end L19.end
  measures "d220" distance of L18.end L21.end
extrude "Extrude8" add sketch "Sketch5" along normal blind 2.5 contours L2 L14 L15 L16 L17
extrude "Extrude9" add sketch "Sketch5" along normal blind 3.75 contours L0 L3 L4 L5 L6 L7 | L0 L1 L9 L10 L11 L12
extrude "Extrude11" add sketch "Sketch5" along normal blind 7.5 contours L0 L19 L20 L21 L22
draft "Draft1" angle -2.75 neutral plane through (79.15, 0, -81.055) pull (1, 0, 0) 1 faces at (-28.8334, -11.8975, -2.7607)
sketch "Sketch7" plane through (-0.388, -8.077, 0) normal (-0.047978, -0.998848, 0) x (0, 0, 1)
  ellipse E0 centre (-74.8678, -73.4354) end of major axis (-74.8678, -75.5127) minor radius 2.075
  ellipse E1 centre (-63.4378, 72.6585) end of major axis (-63.4378, 70.5811) minor radius 2.075
  ellipse E2 centre (106.3813, -59.463) end of major axis (106.3813, -61.5404) minor radius 2.075
  ellipse E3 centre (63.4378, 72.6585) end of major axis (63.4378, 70.5811) minor radius 2.075
  line L0 (-47.15, 66.3635) -> (-47.15, 78.8528)
  line L1 (-47.15, 78.8528) -> (-69.625, 78.8528)
  line L2 (-69.625, 78.8528) -> (-69.625, 21.637)
  line L3 (-69.625, 21.637) -> (-79.15, 21.637)
  line L4 (-79.15, 21.637) -> (-79.15, 2.565)
  line L5 (-79.15, 2.565) -> (-86.77, 2.565)
  line L6 (-86.77, 2.565) -> (-86.77, -41.4857)
  line L7 (-86.77, -41.4857) -> (-81.055, -41.4857)
  line L8 (-81.055, -41.4857) -> (-81.055, -79.6297)
  line L9 (-81.055, -79.6297) -> (-58.58, -79.6297)
  line L10 (-58.58, -79.6297) -> (-58.58, -67.1403)
  line L11 (-58.58, -67.1403) -> (48.0199, -67.1403)
  line L12 (48.0199, -67.1403) -> (59.6321, -65.4867)
  line L13 (59.6321, -65.4867) -> (89.021, -57.6029)
  line L14 (89.021, -57.6029) -> (92.2498, -69.6667)
  line L15 (92.2498, -69.6667) -> (113.959, -63.8431)
  line L16 (113.959, -63.8431) -> (93.5653, 12.3548)
  line L17 (93.5653, 12.3548) -> (69.625, 15.4658)
  line L18 (69.625, 15.4658) -> (69.625, 78.8528)
  line L19 (69.625, 78.8528) -> (47.15, 78.8528)
  line L20 (47.15, 78.8528) -> (47.15, 66.3635)
  line L21 (47.15, 66.3635) -> (-47.15, 66.3635)
  ellipse E4 centre (-49.53, -48.0683) end of major axis (-49.53, -49.8203) minor radius 1.75
  ellipse E5 centre (53.5781, 0.8036) end of major axis (53.5781, -0.9484) minor radius 1.75
  ellipse E6 centre (38.475, 47.2915) end of major axis (38.475, 45.5395) minor radius 1.75
  ellipse E7 centre (-37.725, 47.2915) end of major axis (-37.725, 45.5395) minor radius 1.75
  ellipse E8 centre (51.1969, -54.0283) end of major axis (51.1969, -55.7803) minor radius 1.75
  ellipse E9 centre (-9.525, -9.3738) end of major axis (-9.525, -11.1258) minor radius 1.75
  line L22 (-81.055, -79.6297) -> (-61.055, -79.6297) construction
  line L23 (-61.055, -79.6297) -> (-61.055, -54.6297) construction
  line L24 (-69.625, 78.8528) -> (-49.625, 78.8528) construction
  line L25 (-49.625, 78.8528) -> (-49.625, 53.8528) construction
  line L26 (69.625, 78.8528) -> (49.625, 78.8528) construction
  line L27 (49.625, 78.8528) -> (49.625, 53.8528) construction
  line L28 (113.959, -63.8431) -> (94.642, -69.025) construction
  line L29 (94.642, -69.025) -> (88.1645, -44.8787) construction
  circle A0 centre (88.1645, -44.8787) radius 5
  circle A1 centre (49.625, 53.8528) radius 5
  circle A2 centre (-49.625, 53.8528) radius 5
  circle A3 centre (-61.055, -54.6297) radius 5
  dimension "d229" = 20
  dimension "d230" = 25
  dimension "d231" = 20
  dimension "d232" = 25
  dimension "d233" = 20
  dimension "d234" = 25
  dimension "d235" = 20
  dimension "d236" = 25
  dimension "d237" = 10
  dimension "d238" = 10
  dimension "d239" = 10
  dimension "d240" = 10
  constraint coincident L8.end L9.start
  constraint perpendicular L8 L22
  constraint perpendicular L9 L23
  constraint coincident L1.end L2.start
  constraint coincident L1 L24.end
  constraint perpendicular L1 L25
  constraint coincident L18.end L19.start
  constraint coincident L19 L26.end
  constraint perpendicular L19 L27
  constraint coincident L15.end L16.start
  constraint coincident L15 L28.end
  constraint perpendicular L15 L29
  constraint coincident L29.end A0.centre
  constraint coincident L27.end A1.centre
  constraint coincident L25.end A2.centre
  constraint coincident L23.end A3.centre
  measures "d229" distance of L8.end L22.end
  measures "d230" distance of L22.end L23.end
  measures "d231" distance of L1.end L24.end
  measures "d232" distance of L24.end L25.end
  measures "d233" distance of L18.end L26.end
  measures "d234" distance of L26.end L27.end
  measures "d235" distance of L15.end L28.end
  measures "d236" distance of L28.end L29.end
  measures "d237" diameter of A0
  measures "d238" diameter of A1
  measures "d239" diameter of A2
  measures "d240" diameter of A3
extrude "Extrude13" cut sketch "Sketch7" against normal blind 0.5 contours A0 | A1 | A2 | A3
fillet "Fillet2" radius 2.5 12 edges at (-79.15, -2.1469, 69.625) (-15.8359, -3.6675, 69.625) (-12.7285, -3.7421, 93.5653) (63.3816, -5.57, 113.959) (79.15, -5.9487, -81.055) (41.05, -5.0337, -81.055) (41.05, -5.0337, -86.77) (-2.95, -3.977, -86.77) (-22, -3.5194, -79.15) (-2.95, -3.977, -79.15) (-22, -3.5194, -69.625) (-79.15, -2.1469, -69.625)
equation "sw_size_Ref = 19.05 mm"
equation "sw_cut_size_Ref = 14 mm"
equation "sw_cut_space_Ref = sw_size_Ref - sw_cut_size_Ref"
equation "stab_cut_length_Ref = 6 mm"
equation "stab_cut_height_Ref = 12.5 mm"
equation "stabw_length_Ref = 12 mm" comment "Length of the stabilizer wire per unit (e.g. a 2u stabilizer will be stabilizer_wire_length * 2)"
equation "stabw_height_Ref = 2.5 mm"
equation "stabw_cut_length_Ref = 1.7 mm"
equation "stabw_cut_height_Ref = 1 mm"
equation "plt_thickness_Ref = 1.5 mm"
equation "plt_fillet_Ref = 0.25 mm"
equation "pcb_thickness_Ref = 1.6 mm"
equation "m2scr_diameter_Ref = 2.05 mm"
equation "mtscr_head_diameter_Ref = 3.5 mm"
equation "mtscr_head_width_Ref = 0.5 mm"
equation "ctrl_length_Ref = 33 mm"
equation "ctrl_height_Ref = 18 mm"
equation "ctrl_width_Ref = 1.7 mm"
equation "usbc_length_Ref = 8.34 mm"
equation "usbc_height_Ref = 2.56 mm"
equation "bat_length_Ref = 50 mm"
equation "bat_height_Ref = 34 mm"
equation "bat_width_Ref = 5 mm"
equation "bat_clearance_Ref = 3 mm"
equation "key_size_Ref = 16.5 mm"
equation "key_clearance_Ref = 0.25 mm"
equation "key_space_Ref = sw_size_Ref - ( key_size_Ref + key_clearance_Ref )"
equation "key_fillet_Ref = 1 mm"
equation "thrins_diameter_Ref = 3.5 mm"
equation "thrins_depth_Ref = 2.5 mm"
equation "top_inner_thickness_Ref = 1.5 mm"
equation "plt_up_clearance_Ref = 4.9 mm"
equation "alignh_diameter_Ref = 2.5 mm"
equation "alignh_height_Ref = 5 mm"
equation "case_border_width_Ref = 10 mm"
equation "col_mid_offset_Ref = 0.3 * sw_size_Ref"
equation "col_ring_offset_Ref = 0.4 * sw_size_Ref"
equation "col_pinky_offset_Ref = 0.5 * sw_size_Ref"
equation "stab_vert_offset_Ref = 0.6 mm"
equation "stabw_cut_offset_Ref = 0.835 mm"
equation "plt_border_width_Ref = 2.475 mm"
equation "case_top_thickness_Ref = 4 mm"
equation "top_align_mark_length_Ref = 10 mm"
equation "pcb_clearance_Ref = 8.5 mm"
equation "case_bot_min_thickness_Ref = 3 mm"
equation "case_max_length_Ref = max(7 * sw_size_Ref + plt_border_width_Ref * 2 + case_border_width_Ref * 2; 8 * sw_size_Ref + ( plt_border_width_Ref + case_border_width_Ref ) * 2 + 7.885 mm)"
equation "case_bot_angle_Ref = 2.75 deg"
equation "case_bot_max_thickness_Ref = case_max_length_Ref / tan(90 deg - case_bot_angle_Ref) + case_bot_min_thickness_Ref"
equation "ctrl_socket_height_Ref = 4.191 mm"
equation "bat_wall_thickness_Ref = 2.5 mm"
equation "bat_offset_Ref = 25 mm + bat_wall_thickness_Ref + bat_length_Ref * 0.5"
equation "sw_hotswap_clearance_Ref = 1.9 mm"
equation "d54 = sw_size_Ref * 6"
equation "d55 = sw_size_Ref * 3"
equation "d56 = col_pinky_offset_Ref"
equation "d57 = sw_size_Ref"
equation "d58 = col_ring_offset_Ref"
equation "d59 = sw_size_Ref"
equation "d60 = col_mid_offset_Ref"
equation "d61 = sw_size_Ref * 2"
equation "d62 = sw_size_Ref * 3"
equation "d63 = col_pinky_offset_Ref"
equation "d64 = sw_size_Ref"
equation "d65 = col_ring_offset_Ref - col_mid_offset_Ref"
equation "d68 = ( sw_size_Ref - 18 mm ) * 0.5"
equation "d69 = ( sw_size_Ref - 18 mm ) * 0.5"
equation "d70 = sw_size_Ref"
equation "d71 = sw_size_Ref"
equation "d72 = sw_size_Ref * 2"
equation "d73 = sw_size_Ref * 2"
equation "d74 = sw_size_Ref * 3"
equation "d75 = plt_border_width_Ref"
equation "d76 = plt_border_width_Ref"
equation "d77 = plt_border_width_Ref"
equation "d78 = plt_border_width_Ref"
equation "d79 = plt_border_width_Ref"
equation "d80 = plt_border_width_Ref"
equation "d81 = plt_border_width_Ref"
equation "d82 = plt_border_width_Ref"
equation "d83 = plt_border_width_Ref"